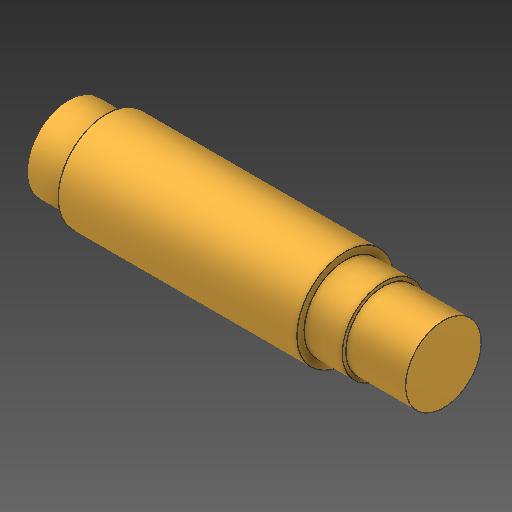
# Autodesk Inventor part: Axixs-Turbine
Saved by Autodesk Inventor 2026.1 (Build 301233020, 233B)
## iProperties
Created: 2026-10-21
Part Number: Axixs-Turbine
Material: Generic
Document SubType Name: Modeling
Designer: YmCris
Density: 1 g/cm^3
Appearance: Default
Author: YmCris
Autodesk Inventor part; units mm, degrees
ref_plane "YZ Plane" through (0, 0, 0) normal (1, 0, 0) x (0, 1, 0)
ref_plane "XZ Plane" through (0, 0, 0) normal (0, 1, 0) x (-1, 0, 0)
ref_plane "XY Plane" through (0, 0, 0) normal (0, 0, 1) x (1, 0, 0)
sketch "Sketch1" plane through (0, 0, 0) normal (0, 0, 1) x (1, 0, 0)
  line L0 (0, 0) -> (0, 17.36)
  line L1 (0, 17.36) -> (16, 17.36)
  line L2 (16, 17.36) -> (16, 20.36)
  line L3 (16, 20.36) -> (116, 20.36)
  line L4 (116, 20.36) -> (116, 17.36)
  line L5 (116, 17.36) -> (132, 17.36)
  line L6 (132, 17.36) -> (132, 15.86)
  line L7 (132, 15.86) -> (157, 15.86)
  line L8 (157, 15.86) -> (157, 0)
  line L9 (157, 0) -> (0, 0)
  line L10 (-31.4, 0) -> (188.4, 0) projected
  dimension "d0" = 17.36
  dimension "d1" = 16
  dimension "d2" = 3
  dimension "d3" = 100
  dimension "d4" = 3
  dimension "d5" = 16
  dimension "d6" = 1.5
  dimension "d8" = 25
  constraints: 20 end point, 3 perpendicular, 2 horizontal, 2 point on line, 1 vertical
  measures "d0" distance of L0.start L0.end
  measures "d1" distance of L0.end L1.end
  measures "d2" distance of L1.end L2.end
  measures "d3" distance of L2.end L3.end
  measures "d4" distance of L3.end L4.end
  measures "d5" distance of L4.end L5.end
  measures "d6" distance of L5.end L6.end
  measures "d8" distance of L6.end L7.end
revolve "Revolution2" add sketch "Sketch1" angle 360 about axis through (-10, 0, 0) along (1, 0, 0)
body "Solid2"
